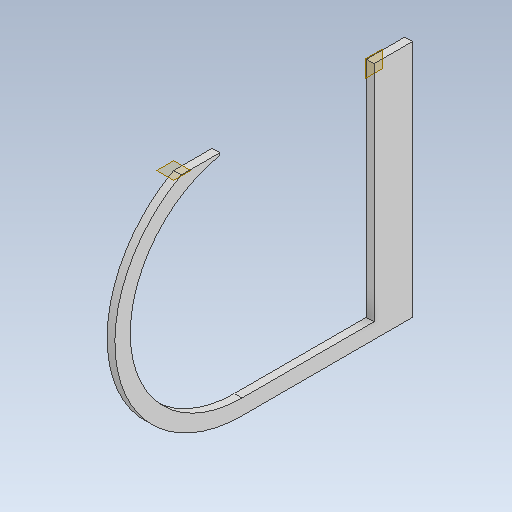
# Autodesk Inventor part: Rotorschutz_SL_BT1
Saved by Autodesk Inventor 2020.1 (Build 241239000, 239)
## iProperties
Created: 2020-08-27
Part Number: Rotorschutz_SL_BT1
Material: Generisch
Document SubType Name: Modeling
Designer: s5chfeis
Density: 1 g/cm^3
Appearance: Vorgabe
Author: s5chfeis
Autodesk Inventor part; units mm, degrees
ref_plane "YZ Plane" through (0, 0, 0) normal (1, 0, 0) x (0, 1, 0)
ref_plane "XZ Plane" through (0, 0, 0) normal (0, 1, 0) x (-1, 0, 0)
ref_plane "XY Plane" through (0, 0, 0) normal (0, 0, 1) x (1, 0, 0)
sketch "Skizze1" plane through (0, 0, 0) normal (0, 1, 0) x (-1, 0, 0)
  line L0 (0, 0) -> (10, 0)
  line L1 (10, 0) -> (10, 50)
  line L2 (10, 50) -> (0, 50)
  line L3 (0, 50) -> (0, 0)
  dimension "d0" = 10
  dimension "d1" = 50
  constraints: 8 end point, 2 parallel, 1 horizontal, 1 perpendicular
  measures "d0" distance of L2.end L1.end
  measures "d1" distance of L1.end L0.end
extrude "Extrusion1" add sketch "Skizze1" along normal blind 300
sketch "Skizze3" plane through (-10, 0, 50) normal (0, 0, 1) x (1, 0, 0)
  line L0 (10, 0) -> (0, 0)
  line L1 (0, 0) -> (0, -20)
  line L2 (0, -20) -> (10, -20)
  line L3 (10, -20) -> (10, 0)
  dimension "d10" = 10
  dimension "d11" = 20
  constraints: 8 end point, 2 parallel, 1 horizontal, 1 perpendicular
  measures "d10" distance of L2.end L1.end
  measures "d11" distance of L1.end L0.end
extrude "Extrusion3" add sketch "Skizze3" along normal blind 171.26
sketch "Skizze4" plane through (-10, 0, 50) normal (0, 0, -1) x (-1, 0, 0)
  line L0 (-10, 0) -> (0, 0)
  line L1 (0, 0) -> (0, -20)
  line L2 (0, -20) -> (-10, -20)
  line L3 (-10, -20) -> (-10, 0)
  dimension "d14" = 10
  dimension "d15" = 20
  constraints: 8 end point, 2 parallel, 1 horizontal, 1 perpendicular
  measures "d14" distance of L1.end L2.end
  measures "d15" distance of L0.end L1.end
extrude "Extrusion4" add sketch "Skizze4" along normal blind 50
ref_plane "Arbeitsebene1" through (0, 290, 50) normal (1, 0, 0) x (0, 0, -1)
sketch "Skizze5" plane through (0, 290, 50) normal (1, 0, 0) x (0, 0, -1)
  line L0 (0, -290) -> (0, 0) construction
  line L1 (0, 0) -> (-400, 0)
  line L2 (0, 0) -> (400, 0) construction
  line L3 (0, -290) -> (-171.26, -290) projected
  line L4 (-171.26, -290) -> (-171.26, -145) construction
  line L5 (-171.26, -290) -> (-26.26, -290) construction
  circle A0 centre (-171.26, -145) radius 145
  circle A1 centre (-171.26, -145) radius 165
  line L6 (-171.26, -290) -> (-171.26, -310) projected
  line L7 (-171.26, -310) -> (-171.26, 20)
  line L8 (-171.26, -310) -> (158.74, -310) construction
  point P0 (50, -290)
  point P1 (-171.26, 0)
  point P2 (-250.0001, 0)
  dimension "d23" = 330
  dimension "d18" = 400
  dimension "d19" = 180
  dimension "d20" = 145
  dimension "d21" = 90
  dimension "d22" = 290
  dimension "d24" = 330
  dimension "d25" = 90
  constraints: 12 end point, 4 horizontal, 3 equal length, 2 coincident, 1 centre point, 1 collinear, 1 vertical, 2 other
  measures "d18" distance of L0.end L1.end
  measures "d19" angle of L1 L2
  measures "d20" distance of L3.end L4.end
  measures "d21" angle of L5 L4
  measures "d22" diameter of A0
  measures "d24" distance of L6.end L7.end
  measures "d25" angle of L8 L7
extrude "Extrusion5" add sketch "Skizze5" against normal blind 10 contours A0 L6 A1 L1
ref_plane "Arbeitsebene3" through (0, 290, 50) normal (1, 0, 0) x (0, 0, -1)
sketch "Skizze6" plane through (0, 290, 50) normal (1, 0, 0) x (0, 0, -1)
  arc A0 (-250.0001, 0) -> (-171.26, -310) centre (-171.26, -145) ccw construction
  line L0 (-250.0001, 0) -> (-200.0001, 0) construction
  line L1 (-250.0001, 0) -> (-171.26, 0) construction
  line L2 (-250.0001, 0) -> (-200.0001, 0) construction
  line L3 (-200.0001, 0) -> (-188.7636, 0)
  line L4 (-188.7636, 0) -> (-188.7636, 19.9811)
  line L5 (-188.7636, 19.9811) -> (-200.0001, 19.9811)
  line L6 (-200.0001, 19.9811) -> (-200.0001, 0)
  line L7 (-200.0001, 0) -> (-188.7636, 0)
  line L8 (-188.7636, 0) -> (-188.7636, -17.2997)
  line L9 (-188.7636, -17.2997) -> (-200.0001, -17.2997)
  line L10 (-200.0001, -17.2997) -> (-200.0001, 0)
  line L11 (-188.7636, 19.9811) -> (-163.1478, 19.9811)
  line L12 (-163.1478, 19.9811) -> (-163.1478, -17.2997)
  line L13 (-163.1478, -17.2997) -> (-188.7636, -17.2997)
  line L14 (-188.7636, -17.2997) -> (-188.7636, 19.9811)
  point P0 (50, -290)
  point P1 (-188.7636, -17.2997)
  dimension "d28" = 50
  dimension "d29" = 0
  constraints: 28 end point, 6 parallel, 4 horizontal, 3 perpendicular, 2 collinear, 1 point on line
  measures "d28" distance of L0.start L0.end
  measures "d29" distance between parallel lines of L0 L2
extrude "Extrusion6" cut sketch "Skizze6" against normal blind 10
ref_plane "Arbeitsebene2" through (-10, 290, 300.0001) normal (0, 1, 0) x (1, 0, 0)
sketch "Skizze10" plane through (0, 300, 50) normal (1, 0, 0) x (0, 0, -1)
  line L0 (50, 0) -> (0, 0)
  line L1 (0, 0) -> (0, -10)
  line L2 (0, -10) -> (50, -10)
  line L3 (50, -10) -> (50, 0)
  point P0 (50, -300)
  dimension "d61" = 50
  dimension "d62" = 10
  constraints: 8 end point, 2 parallel, 1 horizontal, 1 perpendicular
  measures "d61" distance of L2.end L1.end
  measures "d62" distance of L1.end L0.end
extrude "Extrusion8" cut sketch "Skizze10" against normal blind 10
